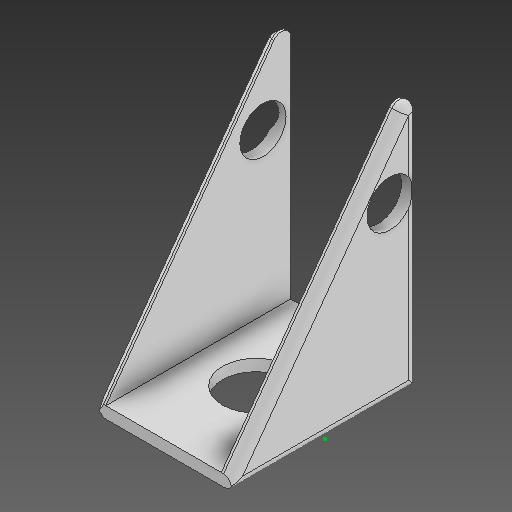
# Autodesk Inventor part: Clamp
Saved by Autodesk Inventor 2026.1 (Build 301233020, 233B)
## iProperties
Created: 2026-09-03
Part Number: Clamp
Material: Generic
Document SubType Name: Modeling
Designer: YmCris
Density: 1 g/cm^3
Appearance: Default
Author: YmCris
Autodesk Inventor part; units mm, degrees
ref_plane "YZ Plane" through (0, 0, 0) normal (1, 0, 0) x (0, 1, 0)
ref_plane "XZ Plane" through (0, 0, 0) normal (0, 1, 0) x (-1, 0, 0)
sketch "Sketch1" plane through (0, 0, 0) normal (0, 1, 0) x (-1, 0, 0)
  line L0 (-15, 20) -> (15, 20)
  line L1 (15, 20) -> (15, -20)
  line L2 (15, -20) -> (-15, -20)
  line L3 (-15, -20) -> (-15, 20)
  line L4 (-15, 20) -> (15, -20) construction
  line L5 (15, 20) -> (-15, -20) construction
  point P0 (0, 0)
  dimension "d0" = 30
  dimension "d1" = 40
  constraints: 12 end point, 2 midpoint, 2 parallel, 1 horizontal, 1 perpendicular
  measures "d0" distance of L1.end L2.end
  measures "d1" distance of L0.end L1.end
extrude "Extrusion1" add sketch "Sketch1" along normal blind 2.5
sketch "Sketch2" plane through (0, 2.5, 0) normal (0, 1, 0) x (1, 0, 0)
  circle A0 centre (0, 0) radius 7.25
  dimension "d4" = 14.5
  constraints: 1 centre point, 1 coincident
  measures "d4" diameter of A0
extrude "Extrusion2" cut sketch "Sketch2" against normal blind 2.5
ref_plane "Work Plane3" through (-15, 0, -20) normal (-1, 0, 0) x (0, 0, 1)
sketch "Sketch3" plane through (-15, 0, -20) normal (-1, 0, 0) x (0, 0, 1)
  line L0 (0, 0) -> (40, 0)
  line L1 (0, 2.5) -> (40, 2.5)
  line L2 (40, 2.5) -> (3.620564, 52.799663)
  line L3 (0, 2.5) -> (0, 51.627583)
  arc A0 (3.620564, 52.799663) -> (0, 51.627583) centre (2, 51.627583) ccw
  point P0 (20, 0)
  point P1 (0, 60)
  dimension "d10" = 60
  dimension "d12" = 2
  constraints: 4 end point, 2 point on circle, 2 tangent, 1 centre point, 1 vertical
  measures "d10" distance of L0.start point (0, 60)
  measures "d12" radius of A0
extrude "Extrusion3" add sketch "Sketch3" against normal blind 2.5
sketch "Sketch4" plane through (-15, 0, -20) normal (-1, 0, 0) x (0, 0, 1)
  circle A0 centre (6.00108, 37.171415) radius 5
  point P0 (20, 0)
  dimension "d15" = 10
  constraints: 1 centre point
  measures "d15" diameter of A0
extrude "Extrusion4" cut sketch "Sketch4" against normal blind 2.5
mirror "Mirror1" about plane through (0, 0, 0) normal (1, 0, 0) of "Extrusion3"
sketch "Sketch5" plane through (15, 0, 20) normal (1, 0, 0) x (0, 0, -1)
  point P0 (20, 0)
sketch "Sketch6" plane through (15, 0, 20) normal (1, 0, 0) x (0, 0, -1)
  circle A0 centre (33.99892, 37.171415) radius 5
  circle A1 centre (33.99892, 37.171415) radius 5
  point P0 (20, 0)
  constraints: 1 centre point, 1 coincident
extrude "Extrusion5" cut sketch "Sketch6" against normal blind 2.5
fillet "Fillet1" radius 2 4 edges at (15, 0, 0) (15, 53.5304, -18.616) (15, 27.6498, 1.8103) (15, 25.8138, -20)
chamfer "Chamfer1" distance 2 angle 45 4 edges at (-15, 0, 0) (-15, 25.8138, -20) (-15, 53.5304, -18.616) (-15, 27.6498, 1.8103)
body "Solid1"
